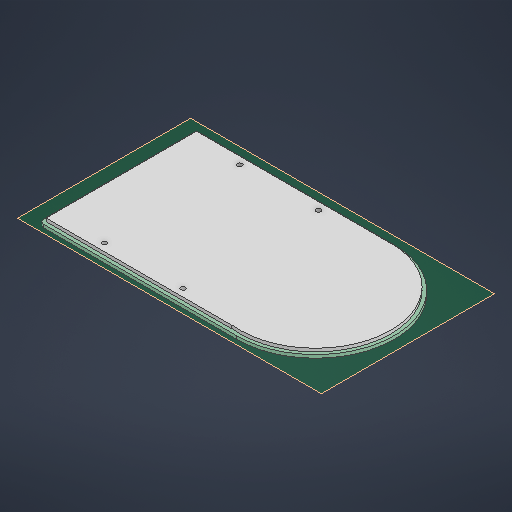
# Autodesk Inventor part: bottom_plate
Saved by Autodesk Inventor 2027 (Build 310192000, 192)
## iProperties
Created: 2026-10-09
Part Number: bottom_plate
Material: Generic
Document SubType Name: Modeling
Designer: Kasper
Density: 1 g/cm^3
Appearance: Default
Author: Kasper
Autodesk Inventor part; units mm, degrees
ref_plane "YZ Plane" through (0, 0, 0) normal (1, 0, 0) x (0, 1, 0)
ref_plane "XZ Plane" through (0, 0, 0) normal (0, 1, 0) x (-1, 0, 0)
ref_plane "XY Plane" through (0, 0, 0) normal (0, 0, 1) x (1, 0, 0)
ref_plane "Work Plane1" through (69.2267, -44.6976, -54.5344) normal (0, -1, 0) x (1, 0, 0)
sketch "Sketch1" plane through (69.2267, -44.6976, -54.5344) normal (0, -1, 0) x (1, 0, 0)
  line L0 (-73.5781, 48) -> (-45.5781, 48) projected
  line L1 (-73.5781, -45) -> (-73.5781, 45) projected
  line L2 (-31.3615, -48) -> (-73.5781, -48) projected
  line L3 (44.6385, -48.0327) -> (44.6385, -48) projected
  arc A0 (47.218, -48.0327) -> (47.218, 48.0327) centre (50, 0) ccw projected
  line L4 (44.6385, 48) -> (44.6385, 48.0327) projected
  line L5 (44.4385, 47.8) -> (-73.3781, 47.8)
  line L6 (-73.3781, 47.8) -> (-73.3781, -47.8)
  line L7 (-73.3781, -47.8) -> (44.4385, -47.8)
  line L8 (44.4385, -47.8) -> (44.4385, -47.5893)
  arc A1 (44.4385, -47.5893) -> (44.4385, 47.5893) centre (50, 0) ccw
  line L9 (44.4385, 47.5893) -> (44.4385, 47.8)
  point P0 (-69.2267, 54.5344)
  point P1 (-45.5781, 48)
  point P2 (-31.3615, -48)
  dimension "d0" = 0.2
  constraints: 10 end point, 2 point on circle, 1 centre point, 7 other
extrude "Extrusion1" add sketch "Sketch1" against normal blind 2
sketch "Sketch4" plane through (69.2267, -44.6976, -54.5344) normal (0, -1, 0) x (1, 0, 0)
  arc A0 (-72.5781, 50) -> (-75.5781, 47) centre (-72.5781, 47) ccw projected
  line L0 (-72.5781, 50) -> (42.4944, 50) projected
  line L1 (-75.5781, -47) -> (-75.5781, 47) projected
  arc A1 (-75.5781, -47) -> (-72.5781, -50) centre (-72.5781, -47) ccw projected
  line L2 (-72.5781, -50) -> (42.4944, -50) projected
  line L3 (42.4944, -50) -> (50, -50) projected
  arc A2 (50, -50) -> (50, 50) centre (50, 0) ccw projected
  line L4 (42.4944, 50) -> (50, 50) projected
  point P0 (-69.2267, 54.5344)
extrude "Extrusion3" add sketch "Sketch4" along normal blind 2
sketch "Sketch3" plane through (69.2267, -46.6976, -54.5344) normal (0, -1, 0) x (1, 0, 0)
  circle A0 centre (-41.0781, -43) radius 1.5 projected
  circle A1 centre (8.9219, -43) radius 1.5 projected
  circle A2 centre (8.9219, 43) radius 1.5 projected
  circle A3 centre (-41.0781, 43) radius 1.5 projected
  point P0 (-69.2267, 54.5344)
extrude "Extrusion2" cut sketch "Sketch3" against normal through all
sketch "Sketch5" plane through (69.2267, -46.6976, -54.5344) normal (0, -1, 0) x (1, 0, 0)
  circle A0 centre (-41.0781, 43) radius 1.5 projected
  circle A1 centre (-41.0781, 43) radius 2.5
  circle A2 centre (8.9219, 43) radius 1.5 projected
  circle A3 centre (8.9219, 43) radius 2.5
  circle A4 centre (8.9219, -43) radius 1.5 projected
  circle A5 centre (8.9219, -43) radius 2.5
  circle A6 centre (-41.0781, -43) radius 1.5 projected
  circle A7 centre (-41.0781, -43) radius 2.5
  point P0 (-69.2267, 54.5344)
  dimension "d7" = 5
  constraints: 4 centre point, 4 coincident, 3 equal radius
  measures "d7" diameter of A1
extrude "Extrusion4" cut sketch "Sketch5" against normal blind 2 contours A0 | A1 | A2 | A3 | A4 | A5 | A6 | A7
body "Solid1"
